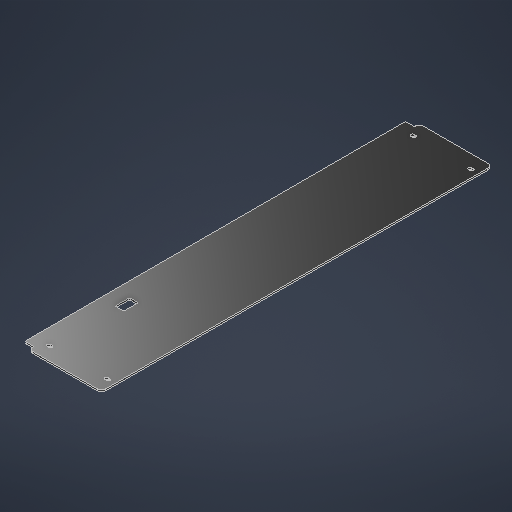
# Autodesk Inventor part: PowerBoxLengthFace
Saved by Autodesk Inventor 2027.1 (Build 311270010, 270A)
## iProperties
Created: 2026-10-13
Part Number: PowerBoxLengthFace
Material: MDF Medium Density Fiberboard
Document SubType Name: Modeling
Designer: SDS Scholar
Density: 0.8 g/cm^3
Appearance: Glossy - Black
Mass: 205.92 g
Surface Area: 1763.64 cm^2
Volume: 257.4 cm^3
Author: SDS Scholar
Autodesk Inventor part; units mm, degrees
ref_plane "YZ Plane" through (0, 0, 0) normal (1, 0, 0) x (0, 1, 0)
ref_plane "XZ Plane" through (0, 0, 0) normal (0, 1, 0) x (-1, 0, 0)
ref_plane "XY Plane" through (0, 0, 0) normal (0, 0, 1) x (1, 0, 0)
sketch "Sketch2" plane through (0, 0, 0) normal (0, 1, 0) x (-1, 0, 0)
  line L0 (55.5, 335) -> (-55.5, 335)
  line L1 (-62.5, 328) -> (-62.5, -328)
  line L2 (-55.5, -335) -> (55.5, -335)
  line L3 (62.5, -328) -> (62.5, 328)
  arc A0 (55.5, -335) -> (62.5, -328) centre (55.5, -328) ccw
  arc A1 (-62.5, -328) -> (-55.5, -335) centre (-55.5, -328) ccw
  arc A2 (62.5, 328) -> (55.5, 335) centre (55.5, 328) ccw
  arc A3 (-55.5, 335) -> (-62.5, 328) centre (-55.5, 328) ccw
  point P0 (0, 0)
  point P1 (62.5, 335)
  point P2 (-62.5, -335)
  point P3 (-62.5, 335)
  point P4 (62.5, -335)
  point P5 (62.5, 0)
  point P6 (0, -335)
  dimension "d4" = 670
  dimension "d5" = 125
  dimension "d37" = 7
  constraints: 8 end point, 8 point on circle, 8 point on line, 8 tangent, 4 centre point, 3 equal radius, 2 midpoint, 2 parallel, 1 horizontal, 1 horizontal alignment, 1 perpendicular, 1 vertical alignment
  measures "d4" distance of point (62.5, -335) point (62.5, 335)
  measures "d5" distance of point (-62.5, -335) point (62.5, -335)
  measures "d37" radius of A0
extrude "Extrusion2" add sketch "Sketch2" along normal blind 3
sketch "Sketch5" plane through (0, 0, 0) normal (0, -1, 0) x (1, 0, 0)
  line L0 (-30.1103, -236.5877) -> (-30.1103, 236.5877) construction
  line L1 (-30.1103, 236.5877) -> (30.1103, 236.5877) construction
  line L2 (30.1103, 236.5877) -> (30.1103, -236.5877) construction
  line L3 (30.1103, -236.5877) -> (-30.1103, -236.5877) construction
  line L4 (62.5, 0) -> (-62.5, 0) construction
  line L5 (-62.5, -328) -> (-62.5, 328) projected
  line L6 (0, 335) -> (0, -335) construction
  line L7 (55.5, -335) -> (-55.5, -335) projected
  spline S0 degree 2 poles (-10.881, -183.3486) (-6.6298, -183.3486) (1.0817, -186.0674) (3.6522, -188.5885) knots 0 0 0 1 2 2 2
  spline S1 degree 2 poles (3.6522, -188.5885) (5.2835, -190.1209) (7.9529, -193.8778) (8.8921, -196.1023) knots 0 0 0 1 2 2 2
  spline S2 degree 2 poles (8.8921, -196.1023) (9.8313, -198.3762) (10.9189, -203.6655) (10.9189, -206.928) knots 0 0 0 1 2 2 2
  line L8 (10.9189, -206.928) -> (10.9189, -214.9361)
  line L9 (10.9189, -214.9361) -> (30.8897, -214.9361)
  line L10 (30.8897, -214.9361) -> (30.8897, -230.2603)
  line L11 (30.8897, -230.2603) -> (-30.1103, -230.2603)
  line L12 (-30.1103, -230.2603) -> (-30.1103, -206.582)
  spline S3 degree 2 poles (-30.1103, -206.582) (-30.1103, -201.3421) (-28.1824, -193.6801) (-26.1063, -190.5658) knots 0 0 0 1 2 2 2
  spline S4 degree 2 poles (-26.1063, -190.5658) (-23.7829, -187.1055) (-16.1703, -183.3486) (-10.881, -183.3486) knots 0 0 0 1 2 2 2
  spline S5 degree 2 poles (-10.4855, -199.0682) (-13.1055, -199.0682) (-16.8129, -201.5399) (-17.505, -203.2206) knots 0 0 0 1 2 2 2
  spline S6 degree 2 poles (-17.505, -203.2206) (-18.4442, -205.3956) (-18.7408, -209.3502) (-18.7408, -212.7611) knots 0 0 0 1 2 2 2
  line L13 (-18.7408, -212.7611) -> (-18.7408, -214.9361)
  line L14 (-18.7408, -214.9361) -> (-0.4507, -214.9361)
  line L15 (-0.4507, -214.9361) -> (-0.4507, -213.8486)
  spline S7 degree 2 poles (-0.4507, -213.8486) (-0.4507, -211.723) (-0.5495, -207.8673) (-0.7967, -206.4337) knots 0 0 0 1 2 2 2
  spline S8 degree 2 poles (-0.7967, -206.4337) (-0.9944, -205.1979) (-2.1808, -202.4791) (-2.9223, -201.7376) knots 0 0 0 1 2 2 2
  spline S9 degree 2 poles (-2.9223, -201.7376) (-4.4053, -200.1558) (-7.7173, -199.0682) (-10.4855, -199.0682) knots 0 0 0 1 2 2 2
  spline S10 degree 2 poles (7.9035, -131.8397) (19.273, -131.8397) (32.3232, -144.2473) (32.3232, -155.5674) knots 0 0 0 1 2 2 2
  spline S11 degree 2 poles (32.3232, -155.5674) (32.3232, -166.8381) (19.273, -179.3446) (7.9035, -179.3446) knots 0 0 0 1 2 2 2
  spline S12 degree 2 poles (7.9035, -179.3446) (-3.5649, -179.3446) (-16.5657, -166.8381) (-16.5657, -155.5674) knots 0 0 0 1 2 2 2
  spline S13 degree 2 poles (-16.5657, -155.5674) (-16.5657, -144.2968) (-3.5155, -131.8397) (7.9035, -131.8397) knots 0 0 0 1 2 2 2
  spline S14 degree 2 poles (8.0023, -146.5212) (3.8994, -146.5212) (-1.5876, -147.8559) (-3.2189, -149.0423) knots 0 0 0 1 2 2 2
  spline S15 degree 2 poles (-3.2189, -149.0423) (-4.9491, -150.3276) (-6.2837, -153.5407) (-6.2837, -155.5674) knots 0 0 0 1 2 2 2
  spline S16 degree 2 poles (-6.2837, -155.5674) (-6.2837, -157.5447) (-5.0973, -160.659) (-3.4166, -161.9442) knots 0 0 0 1 2 2 2
  spline S17 degree 2 poles (-3.4166, -161.9442) (-1.8348, -163.1801) (3.7511, -164.663) (8.0023, -164.663) knots 0 0 0 1 2 2 2
  spline S18 degree 2 poles (8.0023, -164.663) (12.2041, -164.663) (17.3945, -163.2789) (18.9764, -162.142) knots 0 0 0 1 2 2 2
  spline S19 degree 2 poles (18.9764, -162.142) (20.5582, -161.005) (22.0412, -157.5447) (22.0412, -155.4686) knots 0 0 0 1 2 2 2
  spline S20 degree 2 poles (22.0412, -155.4686) (22.0412, -153.7384) (20.5582, -150.1793) (19.0753, -149.0917) knots 0 0 0 1 2 2 2
  spline S21 degree 2 poles (19.0753, -149.0917) (17.3451, -147.8559) (12.3524, -146.5212) (8.0023, -146.5212) knots 0 0 0 1 2 2 2
  line L16 (-15.1322, -55.6639) -> (30.8897, -69.1096)
  line L17 (30.8897, -69.1096) -> (30.8897, -84.3348)
  line L18 (30.8897, -84.3348) -> (1.1312, -92.4418)
  line L19 (1.1312, -92.4418) -> (30.8897, -100.5488)
  line L20 (30.8897, -100.5488) -> (30.8897, -115.7741)
  line L21 (30.8897, -115.7741) -> (-15.1322, -129.1209)
  line L22 (-15.1322, -129.1209) -> (-15.1322, -114.0439)
  line L23 (-15.1322, -114.0439) -> (15.3184, -106.975)
  line L24 (15.3184, -106.975) -> (-15.1322, -98.2749)
  line L25 (-15.1322, -98.2749) -> (-15.1322, -85.5707)
  line L26 (-15.1322, -85.5707) -> (15.3184, -77.3648)
  line L27 (15.3184, -77.3648) -> (-15.1322, -70.3948)
  line L28 (-15.1322, -70.3948) -> (-15.1322, -55.6639)
  spline S22 degree 2 poles (32.1255, -26.0042) (32.1255, -39.0544) (19.6685, -52.945) (8.1506, -52.945) knots 0 0 0 1 2 2 2
  spline S23 degree 2 poles (8.1506, -52.945) (-3.12, -52.945) (-16.5657, -39.9937) (-16.5657, -28.3275) knots 0 0 0 1 2 2 2
  spline S24 degree 2 poles (-16.5657, -28.3275) (-16.5657, -17.7984) (-5.1468, -7.1209) (5.4318, -7.1209) knots 0 0 0 1 2 2 2
  line L29 (5.4318, -7.1209) -> (10.6223, -7.1209)
  line L30 (10.6223, -7.1209) -> (10.6223, -38.6096)
  spline S25 degree 2 poles (10.6223, -38.6096) (13.8354, -38.4118) (18.0866, -36.0885) (19.3719, -34.21) knots 0 0 0 1 2 2 2
  spline S26 degree 2 poles (19.3719, -34.21) (20.6571, -32.381) (21.7446, -27.4378) (21.7446, -24.5212) knots 0 0 0 1 2 2 2
  spline S27 degree 2 poles (21.7446, -24.5212) (21.7446, -22.0496) (20.6571, -17.2052) (19.7179, -15.1784) knots 0 0 0 1 2 2 2
  spline S28 degree 2 poles (19.7179, -15.1784) (18.9764, -13.3989) (17.1474, -10.4329) (16.4553, -9.4937) knots 0 0 0 1 2 2 2
  line L31 (16.4553, -9.4937) -> (16.4553, -7.9613)
  line L32 (16.4553, -7.9613) -> (28.3192, -7.9613)
  spline S29 degree 2 poles (28.3192, -7.9613) (29.0112, -9.7408) (30.1976, -12.6079) (30.7908, -15.1784) knots 0 0 0 1 2 2 2
  spline S30 degree 2 poles (30.7908, -15.1784) (31.4334, -17.5018) (32.1255, -22.445) (32.1255, -26.0042) knots 0 0 0 1 2 2 2
  spline S31 degree 2 poles (1.9715, -21.2587) (-2.5763, -21.3575) (-7.3713, -25.3616) (-7.3713, -29.4645) knots 0 0 0 1 2 2 2
  spline S32 degree 2 poles (-7.3713, -29.4645) (-7.3713, -33.6663) (-2.3291, -38.4118) (1.9715, -38.659) knots 0 0 0 1 2 2 2
  line L33 (1.9715, -38.659) -> (1.9715, -21.2587)
  line L34 (-1.5382, 31.14) -> (-1.5382, 29.9537)
  spline S33 degree 2 poles (-1.5382, 29.9537) (-1.8348, 29.1133) (-2.1314, 25.999) (-2.1314, 24.1206) knots 0 0 0 1 2 2 2
  spline S34 degree 2 poles (-2.1314, 24.1206) (-2.1314, 21.8961) (-0.7967, 16.9034) (0.0931, 14.5801) knots 0 0 0 1 2 2 2
  line L35 (0.0931, 14.5801) -> (30.8897, 14.5801)
  line L36 (30.8897, 14.5801) -> (30.8897, 0.2446)
  line L37 (30.8897, 0.2446) -> (-15.1322, 0.2446)
  line L38 (-15.1322, 0.2446) -> (-15.1322, 14.5801)
  line L39 (-15.1322, 14.5801) -> (-8.5082, 14.5801)
  spline S35 degree 2 poles (-8.5082, 14.5801) (-9.398, 15.5687) (-12.1662, 19.029) (-13.0066, 20.4626) knots 0 0 0 1 2 2 2
  spline S36 degree 2 poles (-13.0066, 20.4626) (-13.9458, 22.0444) (-15.2805, 26.1968) (-15.2805, 28.0258) knots 0 0 0 1 2 2 2
  spline S37 degree 2 poles (-15.2805, 28.0258) (-15.2805, 28.7178) (-15.1816, 30.448) (-15.1322, 31.14) knots 0 0 0 1 2 2 2
  line L40 (-15.1322, 31.14) -> (-1.5382, 31.14)
  spline S38 degree 2 poles (12.2041, 110.7762) (16.7519, 110.7762) (23.6231, 107.3159) (25.897, 104.4488) knots 0 0 0 1 2 2 2
  spline S39 degree 2 poles (25.897, 104.4488) (28.6158, 100.9885) (30.8897, 92.7827) (30.8897, 86.4059) knots 0 0 0 1 2 2 2
  line L41 (30.8897, 86.4059) -> (30.8897, 62.0355)
  line L42 (30.8897, 62.0355) -> (-30.1103, 62.0355)
  line L43 (-30.1103, 62.0355) -> (-30.1103, 83.5388)
  spline S40 degree 2 poles (-30.1103, 83.5388) (-30.1103, 90.2616) (-29.0722, 97.1822) (-27.4409, 100.1976) knots 0 0 0 1 2 2 2
  spline S41 degree 2 poles (-27.4409, 100.1976) (-25.7108, 103.5096) (-19.7789, 106.7227) (-15.9231, 106.7227) knots 0 0 0 1 2 2 2
  spline S42 degree 2 poles (-15.9231, 106.7227) (-11.4742, 106.7227) (-4.5042, 102.2738) (-2.8729, 98.3191) knots 0 0 0 1 2 2 2
  line L44 (-2.8729, 98.3191) -> (-2.5763, 98.3191)
  spline S43 degree 2 poles (-2.5763, 98.3191) (-1.3899, 104.0039) (5.9756, 110.7762) (12.2041, 110.7762) knots 0 0 0 1 2 2 2
  spline S44 degree 2 poles (11.9569, 94.9577) (9.0898, 94.9577) (5.8767, 92.6838) (5.0364, 90.4099) knots 0 0 0 1 2 2 2
  spline S45 degree 2 poles (5.0364, 90.4099) (4.4926, 89.0258) (4.3937, 84.1319) (4.3937, 80.0785) knots 0 0 0 1 2 2 2
  line L45 (4.3937, 80.0785) -> (4.3937, 77.2608)
  line L46 (4.3937, 77.2608) -> (19.7673, 77.2608)
  line L47 (19.7673, 77.2608) -> (19.7673, 78.1011)
  spline S46 degree 2 poles (19.7673, 78.1011) (19.7673, 84.0331) (19.619, 88.5809) (18.5809, 90.9537) knots 0 0 0 1 2 2 2
  spline S47 degree 2 poles (18.5809, 90.9537) (17.6417, 93.0298) (14.1814, 94.9577) (11.9569, 94.9577) knots 0 0 0 1 2 2 2
  spline S48 degree 2 poles (-12.9077, 91.1514) (-14.3907, 91.1514) (-17.505, 89.619) (-18.197, 88.0371) knots 0 0 0 1 2 2 2
  spline S49 degree 2 poles (-18.197, 88.0371) (-18.8891, 86.5541) (-18.988, 82.4018) (-18.988, 78.2989) knots 0 0 0 1 2 2 2
  line L48 (-18.988, 78.2989) -> (-18.988, 77.2608)
  line L49 (-18.988, 77.2608) -> (-6.0366, 77.2608)
  line L50 (-6.0366, 77.2608) -> (-6.0366, 79.1887)
  spline S50 degree 2 poles (-6.0366, 79.1887) (-6.0366, 83.0939) (-6.1849, 86.2576) (-6.9758, 87.9383) knots 0 0 0 1 2 2 2
  spline S51 degree 2 poles (-6.9758, 87.9383) (-7.8656, 89.7673) (-10.881, 91.1514) (-12.9077, 91.1514) knots 0 0 0 1 2 2 2
  spline S52 degree 2 poles (7.9035, 162.8783) (19.273, 162.8783) (32.3232, 150.4707) (32.3232, 139.1506) knots 0 0 0 1 2 2 2
  spline S53 degree 2 poles (32.3232, 139.1506) (32.3232, 127.8799) (19.273, 115.3734) (7.9035, 115.3734) knots 0 0 0 1 2 2 2
  spline S54 degree 2 poles (7.9035, 115.3734) (-3.5649, 115.3734) (-16.5657, 127.8799) (-16.5657, 139.1506) knots 0 0 0 1 2 2 2
  spline S55 degree 2 poles (-16.5657, 139.1506) (-16.5657, 150.4213) (-3.5155, 162.8783) (7.9035, 162.8783) knots 0 0 0 1 2 2 2
  spline S56 degree 2 poles (8.0023, 148.1968) (3.8994, 148.1968) (-1.5876, 146.8621) (-3.2189, 145.6757) knots 0 0 0 1 2 2 2
  spline S57 degree 2 poles (-3.2189, 145.6757) (-4.9491, 144.3905) (-6.2837, 141.1773) (-6.2837, 139.1506) knots 0 0 0 1 2 2 2
  spline S58 degree 2 poles (-6.2837, 139.1506) (-6.2837, 137.1733) (-5.0973, 134.059) (-3.4166, 132.7738) knots 0 0 0 1 2 2 2
  spline S59 degree 2 poles (-3.4166, 132.7738) (-1.8348, 131.5379) (3.7511, 130.055) (8.0023, 130.055) knots 0 0 0 1 2 2 2
  spline S60 degree 2 poles (8.0023, 130.055) (12.2041, 130.055) (17.3945, 131.4391) (18.9764, 132.576) knots 0 0 0 1 2 2 2
  spline S61 degree 2 poles (18.9764, 132.576) (20.5582, 133.713) (22.0412, 137.1733) (22.0412, 139.2495) knots 0 0 0 1 2 2 2
  spline S62 degree 2 poles (22.0412, 139.2495) (22.0412, 140.9796) (20.5582, 144.5388) (19.0753, 145.6263) knots 0 0 0 1 2 2 2
  spline S63 degree 2 poles (19.0753, 145.6263) (17.3451, 146.8621) (12.3524, 148.1968) (8.0023, 148.1968) knots 0 0 0 1 2 2 2
  line L51 (30.8897, 215.8702) -> (30.8897, 199.0631)
  line L52 (30.8897, 199.0631) -> (17.6911, 190.3135)
  line L53 (17.6911, 190.3135) -> (30.8897, 181.3167)
  line L54 (30.8897, 181.3167) -> (30.8897, 164.8556)
  line L55 (30.8897, 164.8556) -> (7.854, 181.811)
  line L56 (7.854, 181.811) -> (-15.1322, 165.1522)
  line L57 (-15.1322, 165.1522) -> (-15.1322, 181.9593)
  line L58 (-15.1322, 181.9593) -> (-2.1808, 190.5606)
  line L59 (-2.1808, 190.5606) -> (-15.1322, 199.2114)
  line L60 (-15.1322, 199.2114) -> (-15.1322, 215.6725)
  line L61 (-15.1322, 215.6725) -> (7.508, 199.0136)
  line L62 (7.508, 199.0136) -> (30.8897, 215.8702)
  point P0 (0, 0)
  point P1 (-70, -74.7)
  point P2 (-70, 5.6)
  point P3 (-30.1103, 0)
  point P4 (27, -315)
  point P5 (-27, -315)
  point P6 (0, -236.5877)
  point P7 (-70, -315)
  point P8 (-70, 315)
  point P9 (70, -315)
  constraints: 4 end point, 4 midpoint, 2 point on line, 1 horizontal, 6 other
emboss "Emboss1" sketch "Sketch5" operation add depth 0.1 direction (0, 1, 0)
sketch "Sketch6" plane through (0, 0, 0) normal (0, -1, 0) x (1, 0, 0)
  line L0 (-37.5, 174) -> (-37.5, 195)
  line L1 (-39.5, 197) -> (-50.5, 197)
  line L2 (-52.5, 195) -> (-52.5, 174)
  line L3 (-50.5, 172) -> (-39.5, 172)
  line L4 (-55.5, 335) -> (55.5, 335) projected
  arc A0 (-52.5, 174) -> (-50.5, 172) centre (-50.5, 174) ccw
  arc A1 (-37.5, 195) -> (-39.5, 197) centre (-39.5, 195) ccw
  arc A2 (-50.5, 197) -> (-52.5, 195) centre (-50.5, 195) ccw
  arc A3 (-39.5, 172) -> (-37.5, 174) centre (-39.5, 174) ccw
  line L5 (-62.5, -328) -> (-62.5, 328) projected
  point P0 (0, 0)
  point P1 (-37.5, 172)
  point P2 (-52.5, 197)
  point P3 (-37.5, 197)
  point P4 (-52.5, 172)
  point P5 (-27, 315)
  point P6 (27, 315)
  point P7 (-70, 315)
  point P8 (70, 315)
  point P9 (-70, -315)
  dimension "d23" = 25
  dimension "d24" = 15
  dimension "d25" = 138
  dimension "d29" = 2
  dimension "d30" = 10
  constraints: 8 end point, 8 point on circle, 8 point on line, 8 tangent, 4 centre point, 3 equal radius, 2 parallel, 1 perpendicular, 2 other
  measures "d23" distance of point (-52.5, 172) point (-52.5, 197)
  measures "d24" distance of point (-52.5, 197) point (-37.5, 197)
  measures "d29" radius of A0
extrude "Extrusion4" cut sketch "Sketch6" against normal through all
sketch "Sketch7" plane through (0, 0, 0) normal (0, -1, 0) x (1, 0, 0)
  line L0 (-50.5, 197) -> (-39.5, 197) projected
  arc A0 (-37.5, 195) -> (-39.5, 197) centre (-39.5, 195) ccw projected
  line L1 (-37.5, 195) -> (-37.5, 174) projected
  arc A1 (-39.5, 172) -> (-37.5, 174) centre (-39.5, 174) ccw projected
  line L2 (-39.5, 172) -> (-50.5, 172) projected
  arc A2 (-52.5, 174) -> (-50.5, 172) centre (-50.5, 174) ccw projected
  line L3 (-52.5, 174) -> (-52.5, 195) projected
  arc A3 (-50.5, 197) -> (-52.5, 195) centre (-50.5, 195) ccw projected
  line L4 (-2.1808, 190.5606) -> (-15.1322, 199.2114) projected
  line L5 (-15.1322, 199.2114) -> (-15.1322, 215.6725) projected
  line L6 (-15.1322, 215.6725) -> (7.508, 199.0136) projected
  line L7 (7.508, 199.0136) -> (30.8897, 215.8702) projected
  line L8 (30.8897, 215.8702) -> (30.8897, 199.0631) projected
  line L9 (30.8897, 199.0631) -> (17.6911, 190.3135) projected
  line L10 (17.6911, 190.3135) -> (30.8897, 181.3167) projected
  line L11 (30.8897, 181.3167) -> (30.8897, 164.8556) projected
  line L12 (30.8897, 164.8556) -> (7.854, 181.811) projected
  line L13 (7.854, 181.811) -> (-15.1322, 165.1522) projected
  line L14 (-15.1322, 165.1522) -> (-15.1322, 181.9593) projected
  line L15 (-15.1322, 181.9593) -> (-2.1808, 190.5606) projected
  line L16 (30.8897, -230.2603) -> (-30.1103, -230.2603) projected
  line L17 (-30.1103, -230.2603) -> (-30.1103, -206.582) projected
  line L18 (10.9189, -206.928) -> (10.9189, -214.9361) projected
  line L19 (10.9189, -214.9361) -> (30.8897, -214.9361) projected
  line L20 (30.8897, -214.9361) -> (30.8897, -230.2603) projected
  line L21 (16.4553, -9.4937) -> (16.4553, -7.9613) projected
  line L22 (16.4553, -7.9613) -> (28.3192, -7.9613) projected
  line L23 (5.4318, -7.1209) -> (10.6223, -7.1209) projected
  line L24 (10.6223, -7.1209) -> (10.6223, -38.6096) projected
  line L25 (-15.1322, 31.14) -> (-1.5382, 31.14) projected
  line L26 (-1.5382, 31.14) -> (-1.5382, 29.9537) projected
  line L27 (0.0931, 14.5801) -> (30.8897, 14.5801) projected
  line L28 (30.8897, 14.5801) -> (30.8897, 0.2446) projected
  line L29 (30.8897, 0.2446) -> (-15.1322, 0.2446) projected
  line L30 (-15.1322, 0.2446) -> (-15.1322, 14.5801) projected
  line L31 (-15.1322, 14.5801) -> (-8.5082, 14.5801) projected
  line L32 (-15.1322, -114.0439) -> (15.3184, -106.975) projected
  line L33 (15.3184, -106.975) -> (-15.1322, -98.2749) projected
  line L34 (-15.1322, -98.2749) -> (-15.1322, -85.5707) projected
  line L35 (-15.1322, -85.5707) -> (15.3184, -77.3648) projected
  line L36 (15.3184, -77.3648) -> (-15.1322, -70.3948) projected
  line L37 (-15.1322, -70.3948) -> (-15.1322, -55.6639) projected
  line L38 (-15.1322, -55.6639) -> (30.8897, -69.1096) projected
  line L39 (30.8897, -69.1096) -> (30.8897, -84.3348) projected
  line L40 (30.8897, -84.3348) -> (1.1312, -92.4418) projected
  line L41 (1.1312, -92.4418) -> (30.8897, -100.5488) projected
  line L42 (30.8897, -100.5488) -> (30.8897, -115.7741) projected
  line L43 (30.8897, -115.7741) -> (-15.1322, -129.1209) projected
  line L44 (-15.1322, -129.1209) -> (-15.1322, -114.0439) projected
  line L45 (-2.8729, 98.3191) -> (-2.5763, 98.3191) projected
  line L46 (30.8897, 86.4059) -> (30.8897, 62.0355) projected
  line L47 (30.8897, 62.0355) -> (-30.1103, 62.0355) projected
  line L48 (-30.1103, 62.0355) -> (-30.1103, 83.5388) projected
  line L49 (62.5, 328) -> (62.5, -328) projected
  line L50 (-55.5, 335) -> (55.5, 335) projected
  line L51 (-62.5, -328) -> (-62.5, 328) projected
  line L52 (55.5, -335) -> (-55.5, -335) projected
  line L53 (-51, -312) -> (-48, -312) construction
  line L54 (-51, -314.9) -> (-48, -314.9)
  line L55 (-48, -309.1) -> (-51, -309.1)
  arc A4 (-51, -309.1) -> (-51, -314.9) centre (-51, -312) ccw
  arc A5 (-48, -314.9) -> (-48, -309.1) centre (-48, -312) ccw
  line L56 (-62.5, 0) -> (62.5, 0) construction
  line L57 (0, 335) -> (0, -335) construction
  line L58 (51, -312) -> (48, -312) construction
  line L59 (51, -314.9) -> (48, -314.9)
  line L60 (48, -309.1) -> (51, -309.1)
  arc A6 (51, -314.9) -> (51, -309.1) centre (51, -312) ccw
  arc A7 (48, -309.1) -> (48, -314.9) centre (48, -312) ccw
  line L61 (-51, 312) -> (-48, 312) construction
  line L62 (-51, 314.9) -> (-48, 314.9)
  line L63 (-48, 309.1) -> (-51, 309.1)
  arc A8 (-51, 314.9) -> (-51, 309.1) centre (-51, 312) ccw
  arc A9 (-48, 309.1) -> (-48, 314.9) centre (-48, 312) ccw
  line L64 (48, 309.1) -> (51, 309.1)
  line L65 (51, 312) -> (48, 312) construction
  line L66 (51, 314.9) -> (48, 314.9)
  arc A10 (51, 309.1) -> (51, 314.9) centre (51, 312) ccw
  arc A11 (48, 314.9) -> (48, 309.1) centre (48, 312) ccw
  arc A12 (-55.5, 335) -> (-62.5, 328) centre (-55.5, 328) ccw projected
  arc A13 (-62.5, -328) -> (-55.5, -335) centre (-55.5, -328) ccw projected
  arc A14 (55.5, -335) -> (62.5, -328) centre (55.5, -328) ccw projected
  arc A15 (62.5, 328) -> (55.5, 335) centre (55.5, 328) ccw projected
  point P0 (0, 0)
  point P1 (-49.5, -312)
  point P2 (49.5, -312)
  point P3 (-49.5, 312)
  point P4 (49.5, 312)
  dimension "d31" = 3
  dimension "d32" = 5.8
  dimension "d33" = 11.5
  dimension "d34" = 23
  constraints: 36 end point, 21 symmetric about line, 16 point on circle, 8 centre point, 5 midpoint, 4 tangent, 1 parallel, 1 perpendicular, 39 other
  measures "d31" distance of L53.start L53.end
  measures "d32" diameter of A5
  measures "d33" distance from line of L51 L53.start
  measures "d34" distance between parallel lines of L52 L53
extrude "Extrusion5" cut sketch "Sketch7" against normal blind 10 contours A4 L55 A5 L54 | L59 A7 L60 A6 | L62 A9 L63 A8 | A11 L66 A10 L64
sketch "Sketch8" plane through (0, 0, 0) normal (0, -1, 0) x (1, 0, 0)
  line L0 (-62.5, -328) -> (-62.5, 328) projected
  line L1 (-77.5, -324.5) -> (-77.5, 324.5)
  line L2 (-62.5, 328) -> (-62.5, -328)
  line L3 (55.5, -335) -> (-55.5, -335) projected
  line L4 (-55.5, 335) -> (55.5, 335) projected
  line L5 (-75.5, -326.5) -> (-62.5, -326.5)
  line L6 (-75.5, 326.5) -> (-62.5, 326.5)
  arc A0 (-75.5, 326.5) -> (-77.5, 324.5) centre (-75.5, 324.5) ccw
  arc A1 (-77.5, -324.5) -> (-75.5, -326.5) centre (-75.5, -324.5) ccw
  point P0 (0, 0)
  point P1 (-77.5, -326.5)
  point P2 (-77.5, 326.5)
  point P3 (-62.5, -326.5)
  point P4 (-62.5, 326.5)
  dimension "d44" = 1.5
  dimension "d45" = 1.5
  dimension "d46" = 15
  dimension "d47" = 2
  constraints: 8 end point, 6 point on line, 4 point on circle, 4 tangent, 2 centre point, 2 perpendicular, 1 equal radius, 1 parallel
  measures "d44" distance from line of L0.start L5
  measures "d45" distance from line of L0.end L6
  measures "d46" distance between parallel lines of L0 L1
  measures "d47" radius of A0
extrude "Extrusion6" add sketch "Sketch8" against normal blind 3
equation "\"d5\" = BoxesWidth"
equation "\"GridProcutClearance\" = 5"
equation "\"GridBorderThickness\" = 5"
equation "\"GridBorderFillets\" = 7"
equation "\"GridTotalSize\" = 65"
equation "\"GridRobotClearance\" = 65"
equation "\"AluminiumExtrusionClearance\" = 35"
equation "\"BaseTotalLength\" = 885"
equation "\"WorkspaceLength\" = 515"
equation "\"WorkspaceHeight\" = 183"
equation "\"AxesBaseFillet\" = 15"
equation "\"Zaxis\" = 197"
equation "\"ProductTotalHeight\" = 45"
equation "\"VerticalStroke\" = 105"
equation "\"BackArea\" = 165"
equation "\"CylinderStroke\" = 75"
equation "\"BoxesWidth\" = 125"
equation "\"BaseWoodThickness\" = 7"
equation "\"kerf\" = 1.5"
equation "\"Kerf\" = 0.3"
equation "\"RxThickness\" = 1.8"
equation "\"support_2\" = 265"
body "Solid2"
